Autodesk Fusion 360 part; units mm, degrees
(part 4 of 4)
  line L516 (-2.1757, 96.675) -> (3.1757, 96.675)
  line L517 (-0.325, 100.1757) -> (-0.325, 94.8243)
  line L518 (-133.0743, 114.497) -> (-138.4257, 114.497)
  line L519 (-134.925, 110.9963) -> (-134.925, 116.3477)
  line L520 (-133.0743, 112.847) -> (-138.4257, 112.847)
  circle A18 centre (-135.75, 113.672) radius 1.65
  line L521 (-136.575, 110.9963) -> (-136.575, 116.3477)
  circle A19 centre (-135.75, 113.672) radius 2.8
  line L522 (-141.25, 45.2198) -> (-126.75, 45.2198)
  line L523 (-126.75, 45.2198) -> (-126.75, 54.4198)
  line L524 (-126.75, 54.4198) -> (-141.25, 54.4198)
  line L525 (-141.25, 54.4198) -> (-141.25, 113.172)
  point P0 (-67.625, 0.0028)
  point P1 (0, 6.0028)
  point P2 (0, 6.0028)
  point P3 (0, 97)
  point P4 (0, 97)
  point P5 (0, 97)
  point P6 (0, 97)
  point P7 (-135.25, 115.5028)
  point P8 (-135.25, 115.5028)
  point P9 (-141.25, 113.172)
  point P10 (-135.25, 119.172)
  dimension "d455" = 5.6
  dimension "d456" = 5.5
  dimension "d457" = 5.5
  dimension "d458" = 3.3
  dimension "d468" = 0.825
  dimension "d469" = 0.825
  dimension "d473" = 0.825
  dimension "d474" = 0.825
  dimension "d482" = 5.6
  dimension "d483" = 3.3
  dimension "d484" = 0.825
  dimension "d485" = 0.825
  dimension "d486" = 0.825
  dimension "d487" = 0.825
  dimension "d488" = 5.5
  dimension "d489" = 5.5
  constraint concentric A12 A13
  constraint coincident A12 L504.start
  constraint coincident A12 L504.end
  constraint horizontal L504
  constraint coincident A12 L505.end
  constraint parallel L504 L505
  constraint coincident A12 L505.start
  constraint coincident A12 L506.start
  constraint coincident A12 L506.end
  constraint vertical L506
  constraint coincident A12 L507.start
  constraint coincident A12 L507.end
  constraint parallel L506 L507
  constraint midpoint L123 P0
  constraint coincident P0 L508.start
  constraint coincident L141 L508.end
  constraint perpendicular L141 L508
  constraint midpoint L142 L509.start
  constraint coincident L138 L509.end
  constraint perpendicular L138 L509
  constraint symmetric A2.centre L508 P2
  constraint symmetric A12 L508 A14
  constraint symmetric A13 L508 A15
  constraint symmetric L504.start L508 L513.start
  constraint symmetric L504.end L508 L513.end
  constraint symmetric L505.start L508 L512.start
  constraint symmetric L505.end L508 L512.end
  constraint symmetric L506.start L508 L511.start
  constraint symmetric L506.end L508 L511.end
  constraint symmetric L507.start L508 L510.start
  constraint symmetric L507.end L508 L510.end
  constraint symmetric P2 L509 P6
  constraint symmetric L509 P2 P6
  constraint symmetric L509 L512.end L516.end
  constraint symmetric L509 L510.start L514.start
  constraint symmetric L509 L511.end L517.end
  constraint symmetric L509 L510.end L514.end
  constraint symmetric L509 L512.start L516.start
  constraint symmetric L509 L513.start L515.start
  constraint symmetric L509 L511.start L517.start
  constraint symmetric L509 L513.end L515.end
  constraint symmetric L509 A14 A17
  constraint symmetric L509 A15 A16
  constraint concentric A18 A19
  constraint coincident L520.start A19
  constraint coincident L520.end A19
  constraint horizontal L520
  constraint coincident L518.end A19
  constraint parallel L518 L520
  constraint coincident L518.start A19
  constraint coincident L519.start A19
  constraint coincident L519.end A19
  constraint vertical L519
  constraint coincident L521.start A19
  constraint coincident L521.end A19
  constraint parallel L519 L521
  measures "d455" diameter of A12
  measures "d456" vertical distance of A2.end A12.centre
  measures "d457" horizontal distance of L122.end A12.centre
  measures "d458" diameter of A13
  measures "d468" distance of A12.centre L504
  measures "d469" distance of A12.centre L505
  measures "d473" distance of A12.centre L506
  measures "d474" distance of A12.centre L507
  measures "d482" diameter of A19
  measures "d483" diameter of A18
  measures "d484" distance of A18.centre L520
  measures "d485" distance of A18.centre L518
  measures "d486" distance of A18.centre L519
  measures "d487" distance of A18.centre L521
  measures "d488" horizontal distance of A18.centre P9
  measures "d489" vertical distance of A18.centre P10
extrude "Extrude10" cut sketch "Screw_Holes" against normal through all contours A13 L505 L506 | A13 L504 L505 L506 | A13 L504 L506 | A13 L505 L506 L507 | L504 L505 L506 L507 | A13 L504 L506 L507 | A13 L505 L507 | A13 L504 L505 L507 | A13 L504 L507 | L510 L511 L513 A15 | L510 L513 A15 | L510 L511 L512 L513 | L510 L512 L513 A15 | L511 L513 A15 | L510 L511 L512 A15 | L510 L512 A15 | L511 L512 L513 A15 | L511 L512 A15 | A16 L514 L515 L516 | A16 L514 L515 | A16 L514 L516 | A16 L514 L515 L517 | L514 L515 L516 L517 | A16 L514 L516 L517 | A16 L515 L517 | A16 L515 L516 L517 | A16 L516 L517 | L518 L519 L520 A18 | L518 L519 A18 | L518 L519 L520 L521 | L518 L519 A18 L521 | L518 L520 A18 L521 | L518 A18 L521 | L519 L520 A18 | L519 L520 A18 L521 | L520 A18 L521 bodies 1 in component "Plate_Left"
extrude "Extrude11" cut sketch "Screw_Holes" against normal blind 3.6 contours A12 A13 L504 L505 | A12 A13 L505 L506 | A12 A13 L504 L506 | A12 A13 L506 L507 | A12 A13 L506 L507 | A12 A13 L505 L507 | A12 A13 L504 L507 | A12 A13 L504 L505 | L510 L511 A14 A15 | L510 L513 A14 A15 | L511 L513 A14 A15 | L512 L513 A14 A15 | L512 L513 A14 A15 | L511 L512 A14 A15 | L510 L512 A14 A15 | L510 L511 A14 A15 | A16 L515 A17 L516 | A16 L514 L515 A17 | A16 L514 A17 L516 | A16 L514 A17 L517 | A16 L514 A17 L517 | A16 L515 A17 L517 | A16 A17 L516 L517 | A16 L515 A17 L516 | L518 L520 A18 A19 | L518 L519 A18 A19 | L519 A18 L521 A19 | L519 L520 A18 A19 | L518 A18 L521 A19 | L519 A18 L521 A19 | L518 L520 A18 A19 | L520 A18 L521 A19 bodies 1 in component "Plate_Left"
chamfer "Chamfer2" distance 1 angle 45 12 edges at (139.4927, -1.7602, 5) (67.625, -0.0028, 5) (-4.2426, -1.7602, 5) (-6, -51.5014, 5) (-4.2426, -101.2426, 5) (41.4233, -103, 5) (83.2614, -103.0435, 5) (101.4852, -111.086, 5) (119.709, -119.1285, 5) (127.6869, -119.172, 5) (139.4927, -117.4146, 5) (141.25, -59.5874, 5) on bodies 1 in component "Plate_Left"
chamfer "Chamfer2" distance 0.4 angle 45 4 edges at (138.3605, -6.5153, 5) (2.1105, -6.5153, 5) (2.1105, -98.5125, 5) (138.3605, -114.6845, 5) on bodies 1 in component "Plate_Left"
sketch "Outline" plane through (0, 0, 0) normal (0, 0, 1) x (1, 0, 0) in component "Base_Left"
  arc A0 (141.25, -6.0028) -> (135.25, -0.0028) centre (135.25, -6.0028) ccw
  line L0 (141.25, -6.0028) -> (141.25, -113.172)
  arc A1 (135.25, -119.172) -> (141.25, -113.172) centre (135.25, -113.172) ccw
  line L1 (135.25, -119.172) -> (120.1238, -119.172)
  arc A2 (119.3123, -118.9999) -> (120.1238, -119.172) centre (120.1238, -117.172) ccw
  line L2 (119.3123, -118.9999) -> (83.6581, -103.172)
  arc A3 (83.6581, -103.172) -> (82.8467, -103) centre (82.8467, -105) ccw
  line L3 (0, -103) -> (82.8467, -103)
  arc A4 (-6, -97) -> (0, -103) centre (0, -97) ccw
  line L4 (-6, -97) -> (-6, -6.0028)
  arc A5 (0, -0.0028) -> (-6, -6.0028) centre (0, -6.0028) ccw
  line L5 (0, -0.0028) -> (135.25, -0.0028)
extrude "Extrude1" add sketch "Outline" against normal blind 7 separate body makes body 2 in component "Base_Left"
shell "Shell1" thickness 3 removed faces 1 at (72.6989, -34.3352, 0) on bodies 2 in component "Base_Left"
sketch "Heatset_Insert" plane through (0, 0, -4) normal (0, 0, 1) x (-1, 0, 0) in component "Base_Left"
  line L0 (-120.3358, 116.172) -> (-135.25, 116.172)
  arc A0 (-135.25, 116.172) -> (-138.25, 113.172) centre (-135.25, 113.172) ccw
  line L1 (-138.25, 113.172) -> (-138.25, 6.0028)
  arc A1 (-138.25, 6.0028) -> (-135.25, 3.0028) centre (-135.25, 6.0028) ccw
  line L2 (-135.25, 3.0028) -> (0, 3.0028)
  arc A2 (0, 3.0028) -> (3, 6.0028) centre (0, 6.0028) ccw
  line L3 (3, 6.0028) -> (3, 97)
  arc A3 (3, 97) -> (0, 100) centre (0, 97) ccw
  line L4 (0, 100) -> (-82.8467, 100)
  arc A4 (-84.8754, 100.4301) -> (-82.8467, 100) centre (-82.8467, 105) ccw
  line L5 (-84.8754, 100.4301) -> (-120.3358, 116.172)
  circle A5 centre (0.5, 5.5028) radius 2.25
  circle A6 centre (-135.75, 5.5028) radius 2.25
  circle A7 centre (0.5, 97.5) radius 2.25
  circle A8 centre (-135.75, 113.672) radius 2.25
  circle A9 centre (0.5, 5.5028) radius 3.375
  circle A10 centre (-135.75, 5.5028) radius 3.375
  circle A11 centre (-135.75, 113.672) radius 3.375
  circle A12 centre (0.5, 97.5) radius 3.375
  point P0 (0.5, 5.5028)
  point P1 (-135.75, 5.5028)
  point P2 (0.5, 97.5)
  point P3 (-135.75, 113.672)
  dimension "d507" = 4.5
  dimension "d508" = 4.5
  dimension "d509" = 4.5
  dimension "d510" = 4.5
  dimension "d511" = 6.75
  dimension "d512" = 6.75
  dimension "d513" = 6.75
  dimension "d514" = 6.75
  constraint coincident P0 A5.centre
  constraint coincident P1 A6.centre
  constraint coincident P2 A7.centre
  constraint coincident P3 A8.centre
  constraint concentric A6 A10
  constraint concentric A8 A11
  constraint concentric A7 A12
  measures "d507" diameter of A5
  measures "d508" diameter of A6
  measures "d509" diameter of A7
  measures "d510" diameter of A8
  measures "d511" diameter of A9
  measures "d512" diameter of A10
  measures "d513" diameter of A11
  measures "d514" diameter of A12
extrude "Extrude2" add sketch "Heatset_Insert" along normal up to surface (4 mm away) contours L0 A0 L1 A11 | L1 A1 L2 A10 | L3 A3 L4 A12 | L2 A2 L3 A9 picked at (-134.4526, 115.9881) picked at (-134.4526, 3.1866) picked at (-0.7975, 99.8162) picked at (-0.7975, 3.1866) bodies 2 in component "Base_Left"
extrude "Extrude4'" cut sketch "Sketch10" against normal up to surface (3 mm away) contours L0 L4 L6 A2 L7 A3 L8 L9 bodies 2 in component "Base_Left"
extrude "Extrude5'" cut sketch "USB_C_MCU" against normal up to surface (3 mm away) contours L1 L4 L6 A0 A1 A2 L7 A3 bodies 2 in component "Base_Left"
move_face "OffsetFaces1'" offset -0.1 4 faces at (140.25, -54.3198, -0.125) (124.5779, -1.0028, -2.65) (119.175, -2.0028, -0.0411) (127.8759, -2.0028, -0.2159) on bodies 2 in component "Base_Left"
chamfer "Chamfer2'" distance 1 angle 45 12 edges at (141.25, -59.5874, -7) (139.4927, -117.4146, -7) (127.6869, -119.172, -7) (119.709, -119.1285, -7) (101.4852, -111.086, -7) (83.2614, -103.0435, -7) (41.4233, -103, -7) (-4.2426, -101.2426, -7) (-6, -51.5014, -7) (-4.2426, -1.7602, -7) (67.625, -0.0028, -7) (139.4927, -1.7602, -7) on bodies 2 in component "Base_Left"
sketch "Feet" plane through (0, 0, -7) normal (0, 0, -1) x (1, 0, 0) in component "Base_Left"
  line L0 (140.25, 6.0028) -> (140.25, 113.172)
  arc A0 (140.25, 113.172) -> (135.25, 118.172) centre (135.25, 113.172) ccw
  line L1 (135.25, 118.172) -> (120.1238, 118.172)
  arc A1 (120.1238, 118.172) -> (119.7181, 118.0859) centre (120.1238, 117.172) ccw
  line L2 (119.7181, 118.0859) -> (84.0639, 102.258)
  arc A2 (82.8467, 102) -> (84.0639, 102.258) centre (82.8467, 105) ccw
  line L3 (82.8467, 102) -> (0, 102)
  arc A3 (0, 102) -> (-5, 97) centre (0, 97) ccw
  line L4 (-5, 97) -> (-5, 6.0028)
  arc A4 (-5, 6.0028) -> (0, 1.0028) centre (0, 6.0028) ccw
  line L5 (0, 1.0028) -> (135.25, 1.0028)
  arc A5 (135.25, 1.0028) -> (140.25, 6.0028) centre (135.25, 6.0028) ccw
  circle A6 centre (133.5, 7.7528) radius 4.75
  line L6 (67.625, 1.0028) -> (67.625, 102)
  line L7 (-5, 51.5014) -> (140.25, 51.5014)
  circle A7 centre (1.75, 7.7528) radius 4.75
  circle A8 centre (1.75, 95.25) radius 4.75
  circle A9 centre (133.5, 111.422) radius 4.75
  dimension "d531" = 9.5
  dimension "d532" = 6.75
  dimension "d533" = 6.75
  dimension "d534" = 9.5
  dimension "d535" = 6.75
  dimension "d536" = 6.75
  constraint midpoint L5 L6.start
  constraint coincident L3 L6.end
  constraint perpendicular L3 L6
  constraint midpoint L4 L7.start
  constraint coincident L0 L7.end
  constraint perpendicular L0 L7
  constraint symmetric A6 L6 A7
  constraint symmetric L7 A7 A8
  measures "d531" diameter of A6
  measures "d532" horizontal distance of L0.start A6.centre
  measures "d533" vertical distance of L5.end A6.centre
  measures "d534" diameter of A9
  measures "d535" vertical distance of A0.end A9.centre
  measures "d536" horizontal distance of L0.end A9.centre
extrude "Extrude7'" cut sketch "Feet" against normal blind 2 contours A6 | A7 | A8 | A9 bodies 2 in component "Base_Left"
chamfer "Chamfer3" distance 1 angle 45 4 edges at (129.0715, -113.1396, -7) (129.0715, -9.4705, -7) (-2.6785, -96.9677, -7) (-2.6785, -9.4705, -7) on bodies 2 in component "Base_Left"
ref_plane "WorkPlane1" through (166.25, -59.5874, -3) normal (1, 0, 0) x (0, -1, 0)
mirror "Mirror1" about plane through (166.25, -59.5874, -3) normal (1, 0, 0) of bodies 1 makes body 3 in component "Plate_Left"
copy_body "CutPasteBodies1" bodies 3 removing the originals makes body 4 in component "Plate_Right"
mirror "Mirror1'" about plane through (166.25, -59.5874, -3) normal (1, 0, 0) of bodies 2 makes body 5 in component "Base_Left"
copy_body "CutPasteBodies1'" bodies 5 removing the originals makes body 6 in component "Base_Right"
component "Plate_Left" placed x (1, 0, 0) y (0, 1, 0) z (0, 0, 1) at (0, 0, 0)
component "Base_Left" placed x (1, 0, 0) y (0, 1, 0) z (0, 0, 1) at (0, 0, 0)
component "Plate_Right" placed x (1, 0, 0) y (0, 1, 0) z (0, 0, 1) at (0, 0, 0) in component "Plate_Left"
component "Base_Right" placed x (1, 0, 0) y (0, 1, 0) z (0, 0, 1) at (0, 0, 0) in component "Base_Left"
equation "switchPlateHole = 14 mm"
equation "switchPlateHoleSpacing = 19.05 mm"
equation "d47 = switchPlateHole"
equation "d48 = switchPlateHole"
equation "d49 = switchPlateHole"
equation "d50 = switchPlateHole"
equation "d51 = switchPlateHoleSpacing"
equation "d52 = switchPlateHole"
equation "d53 = switchPlateHole"
equation "d54 = switchPlateHole"
equation "d55 = switchPlateHole"
equation "d56 = switchPlateHole"
equation "d57 = switchPlateHole"
equation "d58 = switchPlateHoleSpacing"
equation "d59 = switchPlateHoleSpacing"
equation "d60 = switchPlateHoleSpacing"
equation "d61 = switchPlateHole"
equation "d62 = switchPlateHole"
equation "d63 = switchPlateHole"
equation "d64 = switchPlateHole"
equation "d65 = switchPlateHoleSpacing"
equation "d66 = switchPlateHole"
equation "d67 = switchPlateHole"
equation "d68 = switchPlateHole"
equation "d69 = switchPlateHole"
equation "d70 = switchPlateHole"
equation "d71 = switchPlateHole"
equation "d72 = switchPlateHoleSpacing"
equation "d73 = switchPlateHoleSpacing"
equation "d74 = switchPlateHoleSpacing"
equation "d75 = switchPlateHole"
equation "d76 = switchPlateHole"
equation "d77 = switchPlateHole"
equation "d78 = switchPlateHole"
equation "d79 = switchPlateHoleSpacing"
equation "d80 = switchPlateHole"
equation "d81 = switchPlateHole"
equation "d82 = switchPlateHole"
equation "d83 = switchPlateHole"
equation "d84 = switchPlateHole"
equation "d85 = switchPlateHole"
equation "d86 = switchPlateHoleSpacing"
equation "d87 = switchPlateHoleSpacing"
equation "d88 = switchPlateHoleSpacing"
equation "d89 = switchPlateHole"
equation "d90 = switchPlateHole"
equation "d91 = switchPlateHole"
equation "d92 = switchPlateHole"
equation "d93 = switchPlateHoleSpacing"
equation "d94 = switchPlateHole"
equation "d95 = switchPlateHole"
equation "d96 = switchPlateHole"
equation "d97 = switchPlateHole"
equation "d98 = switchPlateHole"
equation "d99 = switchPlateHole"
equation "d100 = switchPlateHoleSpacing"
equation "d101 = switchPlateHoleSpacing"
equation "d102 = switchPlateHoleSpacing"
equation "d103 = switchPlateHole"
equation "d104 = switchPlateHole"
equation "d105 = switchPlateHole"
equation "d106 = switchPlateHole"
equation "d107 = switchPlateHoleSpacing"
equation "d108 = switchPlateHole"
equation "d109 = switchPlateHole"
equation "d110 = switchPlateHole"
equation "d111 = switchPlateHole"
equation "d114 = switchPlateHoleSpacing"
equation "d115 = switchPlateHoleSpacing"
equation "d117 = switchPlateHole"
equation "d118 = switchPlateHole"
equation "d119 = switchPlateHole"
equation "d120 = switchPlateHole"
equation "d121 = switchPlateHoleSpacing"
equation "d122 = switchPlateHole"
equation "d123 = switchPlateHole"
equation "d124 = switchPlateHole"
equation "d125 = switchPlateHole"
equation "d128 = switchPlateHoleSpacing"
equation "d129 = switchPlateHoleSpacing"
equation "rowOffset0 = rowOffset3 + 5.90 mm"
equation "rowOffset1 = rowOffset3 + 4.76 mm"
equation "rowOffset2 = rowOffset3 + 1.14 mm"
equation "rowOffset3 = oneUnitKey / 2 - 7.05 mm"
equation "rowOffset4 = rowOffset3 + 1.14 mm"
equation "rowOffset5 = rowOffset3 + 3.80 mm"
equation "d149 = switchPlateHoleSpacing"
equation "d150 = switchPlateHoleSpacing"
equation "d151 = switchPlateHoleSpacing"
equation "thumbRotation = -30 deg"
equation "d156 = switchPlateHoleSpacing + 8 mm"
equation "d160 = switchPlateHole"
equation "d161 = switchPlateHole"
equation "d163 = switchPlateHoleSpacing + 5.5 mm"
equation "d164 = switchPlateHole"
equation "d165 = switchPlateHole"
equation "d166 = switchPlateHoleSpacing + 3.5 mm"
equation "d168 = switchPlateHoleSpacing + 12.50 mm"
equation "oneUnitKey = 19 mm"
equation "d173 = oneUnitKey"
equation "d174 = oneUnitKey"
equation "d175 = oneUnitKey * 1.5"
equation "d176 = oneUnitKey"
equation "d177 = oneUnitKey"
equation "d178 = oneUnitKey * 1.5"
equation "d179 = oneUnitKey"
equation "d180 = oneUnitKey"
equation "d181 = oneUnitKey"
equation "d182 = oneUnitKey"
equation "d183 = oneUnitKey"
equation "d184 = oneUnitKey"
equation "d185 = oneUnitKey"
equation "d186 = oneUnitKey"
equation "d187 = oneUnitKey"
equation "d188 = oneUnitKey"
equation "d190 = rowOffset0"
equation "d191 = rowOffset1"
equation "d192 = rowOffset2"
equation "d194 = rowOffset4"
equation "d195 = rowOffset5"
equation "d196 = rowOffset3 + 7.05 mm"
equation "d204 = switchPlateHoleSpacing"
equation "d205 = switchPlateHoleSpacing"
equation "d208 = oneUnitKey"
equation "d209 = oneUnitKey"
equation "d210 = oneUnitKey"
equation "d211 = oneUnitKey"
equation "d320 = -5 mm + 1.4 mm"
equation "d455 = screwHead"
equation "d458 = screwShaft"
equation "screwHead = 5.6 mm"
equation "screwShaft = 3.3 mm"
equation "screwHeadDepth = 3 mm"
equation "heatsetInsertSize = 4.5 mm"
equation "d464 = -screwHeadDepth - 0.6 mm"
equation "d468 = screwShaft / 4"
equation "d469 = screwShaft / 4"
equation "d473 = screwShaft / 4"
equation "d474 = screwShaft / 4"
equation "d481 = 4.5 mm + 4 mm"
equation "d482 = screwHead"
equation "d483 = screwShaft"
equation "d484 = screwShaft / 4"
equation "d485 = screwShaft / 4"
equation "d486 = screwShaft / 4"
equation "d487 = screwShaft / 4"
equation "d507 = heatsetInsertSize"
equation "d508 = heatsetInsertSize"
equation "d509 = heatsetInsertSize"
equation "d510 = heatsetInsertSize"
equation "d511 = heatsetInsertSize * 1.5"
equation "d512 = heatsetInsertSize * 1.5"
equation "d513 = heatsetInsertSize * 1.5"
equation "d514 = heatsetInsertSize * 1.5"
equation "feetSize = 9.5 mm"
equation "feetDepth = 2 mm"
equation "d531 = feetSize"
equation "d532 = feetSize / 2 + 2 mm"
equation "d533 = d532"
equation "d534 = feetSize"
equation "d535 = d532"
equation "d536 = d532"
equation "d537 = -feetDepth"
